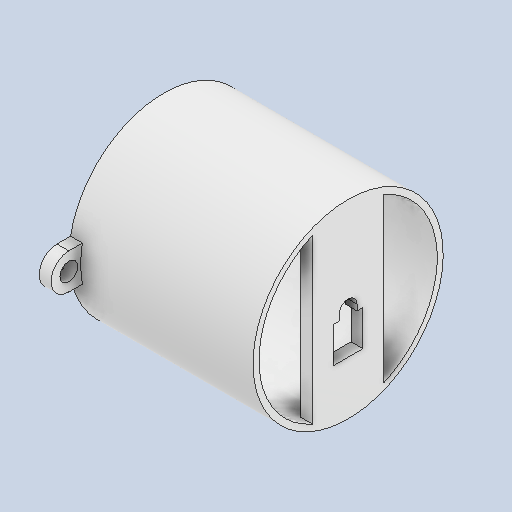
# Autodesk Inventor part: cylinder
Saved by Autodesk Inventor 2026.1 (Build 301233020, 233B)
## iProperties
Created: 2025-12-09
Part Number: cylinder
Material: Plastica ABS
Document SubType Name: Modeling
Designer: maxbu
Density: 1.06 g/cm^3
Appearance: Liscia - Bianco
Mass: 3.94834 g
Surface Area: 71.2025 cm^2
Volume: 3.72485 cm^3
Author: maxbu
Autodesk Inventor part; units mm, degrees
ref_plane "YZ Plane" through (0, 0, 0) normal (1, 0, 0) x (0, 1, 0)
ref_plane "XZ Plane" through (0, 0, 0) normal (0, 1, 0) x (-1, 0, 0)
ref_plane "XY Plane" through (0, 0, 0) normal (0, 0, 1) x (1, 0, 0)
sketch "Schizzo1" plane through (0, 0, 0) normal (1, 0, 0) x (0, 1, 0)
  circle A0 centre (0, 0) radius 16
  circle A1 centre (0, 0) radius 15
  dimension "d0" = 32
  dimension "d1" = 30
  constraints: 2 centre point, 2 coincident
  measures "d0" diameter of A0
  measures "d1" diameter of A1
extrude "Estrusione1" add sketch "Schizzo1" along normal blind 31
sketch "Schizzo2" plane through (0, 0, 0) normal (1, 0, 0) x (0, 1, 0)
  circle A0 centre (0, -18) radius 1.5
  arc A1 (-3, -18) -> (3, -18) centre (0, -18) ccw
  line L0 (3, -18) -> (3, -15.7162)
  line L1 (-3, -18) -> (-3, -15.7162)
  circle A2 centre (0, 0) radius 16 projected
  circle A3 centre (0, 0) radius 15 projected
  line L2 (0, -18) -> (0, 0) construction
  line L3 (0, 0) -> (16, 0) construction
  circle A4 centre (0, 18) radius 1.5
  arc A5 (3, 18) -> (-3, 18) centre (0, 18) ccw
  line L4 (3, 18) -> (3, 15.7162)
  line L5 (-3, 18) -> (-3, 15.7162)
  dimension "d4" = 3
  dimension "d5" = 3
  dimension "d19" = 18
  constraints: 12 end point, 7 point on circle, 6 symmetric about line, 4 centre point, 3 vertical, 2 coincident, 2 tangent, 1 horizontal, 2 other
  measures "d4" radius of A1
  measures "d5" diameter of A0
  measures "d19" distance of point (0, 0) A0.centre
extrude "Estrusione2" add sketch "Schizzo2" along normal blind 2 contours L1 A2 L0 A1 | L5 A5 L4 A2
sketch "Schizzo3" plane through (31, 0, 0) normal (1, 0, 0) x (0, 0, -1)
  circle A0 centre (0, 0) radius 15 projected
  line L0 (-6, 13.7477) -> (-6, -13.7477)
  arc A1 (1.5, 0) -> (-1.5, 0) centre (0, 0) ccw
  line L1 (6, -13.7477) -> (6, 13.7477)
  line L2 (0, 0) -> (1.5, 0) construction
  line L3 (1.5, 0) -> (1.5, -1)
  line L4 (1.5, -1) -> (2.5, -1)
  line L5 (2.5, -1) -> (2.5, -7)
  line L6 (2.5, -7) -> (-2.5, -7)
  line L7 (-2.5, -7) -> (-2.5, -1)
  line L8 (-2.5, -1) -> (-1.5, -1)
  line L9 (-1.5, -1) -> (-1.5, 0)
  line L10 (-1.5, 0) -> (-6, 0) construction
  line L11 (1.5, 0) -> (6, 0) construction
  dimension "d10" = 3
  dimension "d12" = 12
  dimension "d14" = 5
  dimension "d15" = 1
  dimension "d18" = 7
  constraints: 24 end point, 6 point on circle, 5 perpendicular, 2 collinear, 2 midpoint, 2 point on line, 2 tangent, 2 vertical, 1 centre point, 1 coincident, 1 horizontal
  measures "d10" diameter of A1
  measures "d12" distance between parallel lines of L1 L0
  measures "d14" distance between parallel lines of L5 L7
  measures "d15" distance of L2.end L3.end
  measures "d18" distance between parallel lines of L6 L10
extrude "Estrusione3" add sketch "Schizzo3" against normal blind 2 contours L1 A0 L0
